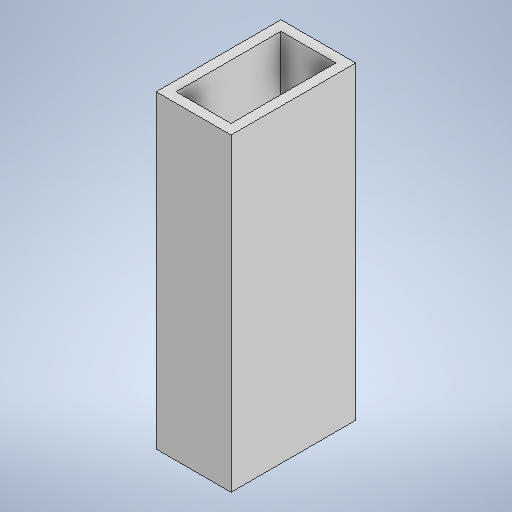
# Autodesk Inventor part: Semesterprojekt1magnetpakkholder
Saved by Autodesk Inventor 2027.1 (Build 311270010, 270A)
## iProperties
Created: 2026-10-21
Part Number: Semesterprojekt1magnetpakkholder
Material: Generic
Document SubType Name: Modeling
Designer: Sif Isaksen
Density: 1 g/cm^3
Appearance: Default
Author: Sif Isaksen
Autodesk Inventor part; units mm, degrees
ref_plane "YZ Plane" through (0, 0, 0) normal (1, 0, 0) x (0, 1, 0)
ref_plane "XZ Plane" through (0, 0, 0) normal (0, 1, 0) x (-1, 0, 0)
ref_plane "XY Plane" through (0, 0, 0) normal (0, 0, 1) x (1, 0, 0)
sketch "Sketch1" plane through (0, 0, 0) normal (0, 1, 0) x (-1, 0, 0)
  line L0 (11.1048, 21.3665) -> (0.1048, 21.3665)
  line L1 (0.1048, 21.3665) -> (0.1048, 0.3665)
  line L2 (0.1048, 0.3665) -> (11.1048, 0.3665)
  line L3 (11.1048, 0.3665) -> (11.1048, 21.3665)
  line L4 (13.1048, 23.3665) -> (-1.8952, 23.3665)
  line L5 (-1.8952, 23.3665) -> (-1.8952, -1.6335)
  line L6 (-1.8952, -1.6335) -> (13.1048, -1.6335)
  line L7 (13.1048, -1.6335) -> (13.1048, 23.3665)
  point P0 (0, 0)
  point P1 (11.1048, 10.8665)
  dimension "d0" = 11
  dimension "d1" = 21
  dimension "d2" = 15
  dimension "d3" = 25
  dimension "d4" = 2
  dimension "d5" = 2
  constraints: 16 end point, 4 parallel, 2 horizontal, 2 perpendicular, 1 midpoint
  measures "d0" distance of L2.end L1.end
  measures "d1" distance of L1.end L0.end
  measures "d2" distance of L6.end L5.end
  measures "d3" distance of L5.end L4.end
  measures "d4" distance from line of L7 point (11.105, 10.866)
  measures "d5" distance between parallel lines of L4 L0
extrude "Extrusion1" add sketch "Sketch1" along normal blind 62
body "Solid1"
